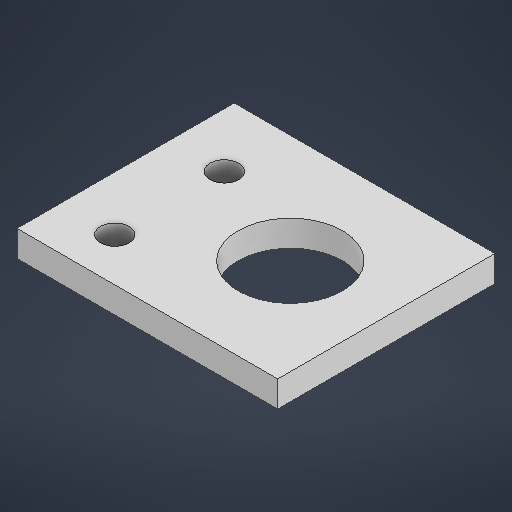
# Autodesk Inventor part: emergencystop
Saved by Autodesk Inventor 2026 (Build 300175000, 175)
## iProperties
Created: 2026-09-17
Part Number: emergencystop
Material: Generic
Document SubType Name: Modeling
Designer: Nitro
Density: 1 g/cm^3
Appearance: Default
Author: Nitro
Autodesk Inventor part; units mm, degrees
ref_plane "YZ Plane" through (0, 0, 0) normal (1, 0, 0) x (0, 1, 0)
ref_plane "XZ Plane" through (0, 0, 0) normal (0, 1, 0) x (-1, 0, 0)
ref_plane "XY Plane" through (0, 0, 0) normal (0, 0, 1) x (1, 0, 0)
sketch "Sketch1" plane through (0, 0, 0) normal (0, 1, 0) x (-1, 0, 0)
  line L0 (0, 0) -> (60, 0)
  line L1 (60, 0) -> (60, 50)
  line L2 (60, 50) -> (0, 50)
  line L3 (0, 50) -> (0, 0)
  circle A0 centre (47.5, 14.8) radius 3.3
  circle A1 centre (47.5, 40) radius 3.3
  circle A2 centre (22.1, 25) radius 12
  dimension "d0" = 50
  dimension "d1" = 60
  dimension "d4" = 6.6
  dimension "d6" = 6.6
  dimension "d7" = 25.2
  dimension "d8" = 47.5
  dimension "d10" = 24
  constraints: 8 end point, 3 centre point, 2 parallel, 1 horizontal, 1 perpendicular
  measures "d0" distance of L0.end L1.end
  measures "d1" distance of L1.end L2.end
  measures "d4" diameter of A0
  measures "d6" diameter of A1
  measures "d7" distance of A1.centre A0.centre
  measures "d8" distance from line of L3 A1.centre
  measures "d10" diameter of A2
extrude "Extrusion1" add sketch "Sketch1" along normal blind 6
body "Solid1"
